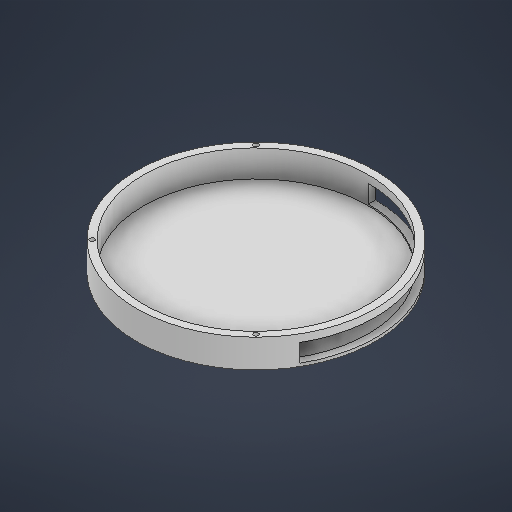
# Autodesk Inventor part: base
Saved by Autodesk Inventor 2027.1 (Build 311270010, 270A)
## iProperties
Created: 2026-11-24
Part Number: base
Material: Ogólny
Document SubType Name: Modeling
Designer: User
Density: 1 g/cm^3
Appearance: Domyślna
Author: User
Autodesk Inventor part; units mm, degrees
ref_plane "YZ Plane" through (0, 0, 0) normal (1, 0, 0) x (0, 1, 0)
ref_plane "XZ Plane" through (0, 0, 0) normal (0, 1, 0) x (-1, 0, 0)
ref_plane "XY Plane" through (0, 0, 0) normal (0, 0, 1) x (1, 0, 0)
sketch "Szkic1" plane through (0, 0, 0) normal (0, 1, 0) x (-1, 0, 0)
  circle A0 centre (0, 0) radius 75.2
  circle A1 centre (0, 0) radius 80
  line L0 (0, 0) -> (-54.8715, 54.8715) construction
  line L1 (0, 0) -> (-75.2, 0) construction
  circle A2 centre (-54.8715, 54.8715) radius 1.6
  circle A3 centre (-54.8715, -54.8715) radius 1.6
  circle A4 centre (54.8715, -54.8715) radius 1.6
  circle A5 centre (54.8715, 54.8715) radius 1.6
  dimension "d0" = 150.4
  dimension "d1" = 160
  dimension "d10" = 77.6
  dimension "d11" = 45
  dimension "d12" = 3.2
  dimension "d15" = 360
  constraints: 5 centre point, 4 end point, 3 coincident, 1 horizontal, 1 horizontal alignment, 11 other
  measures "d1" diameter of A1
  measures "d10" distance of L0.start L0.end
  measures "d11" angle of L1 L0
  measures "d12" diameter of A2
extrude "Wyciągnięcie proste1" add sketch "Szkic1" against normal blind 1 contours A0 | A1 | A3
extrude "Wyciągnięcie proste2" add sketch "Szkic1" along normal blind 18 contours A1 | A3
sketch "Szkic2" plane through (0, 0, 0) normal (1, 0, 0) x (0, 1, 0)
  line L0 (0, 0) -> (0, -75.2)
  line L1 (18, -75.2) -> (0, -75.2) projected
  line L2 (0, -75.2) -> (7, -75.2)
  line L3 (1, -70.2) -> (1, -80.2)
  line L4 (1, -80.2) -> (13, -80.2)
  line L5 (13, -80.2) -> (13, -70.2)
  line L6 (13, -70.2) -> (1, -70.2)
  line L7 (1, -70.2) -> (13, -80.2) construction
  line L8 (1, -80.2) -> (13, -70.2) construction
  line L9 (-3.6, 0) -> (21.6, 0) projected
  dimension "d6" = 7
  dimension "d7" = 10
  dimension "d8" = 12
  constraints: 16 end point, 2 midpoint, 2 parallel, 2 perpendicular, 2 point on line, 1 vertical
  measures "d6" distance of L0.end L2.end
  measures "d7" distance of L3.start L3.end
  measures "d8" distance of L4.end L3.end
revolve "Obrót1" cut sketch "Szkic2" angle 120 about axis through (0, -10, 0) along (0, -1, 0)
equation "\"d0\" = Lamp_dia + Shrink_buffer"
equation "\"d1\" = Base_wall_dia"
equation "\"d10\" = 0.25 * Lamp_dia + 0.25 * Shrink_buffer + 0.25 * Base_wall_dia"
equation "\"d12\" = insert_dia"
equation "\"Shrink_buffer\" = 0.4"
equation "\"Base_wall_dia\" = 160"
equation "\"insert_dia\" = 3.2"
equation "\"Lamp_dia\" = 150"
